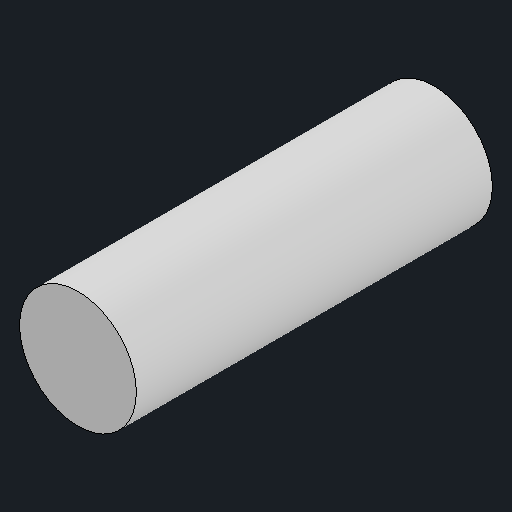
# Autodesk Inventor part: ASH125-bellows-grip-envelope
Saved by Autodesk Inventor 2027.1 (Build 311270010, 270A)
## iProperties
Created: 2026-11-14
Part Number: ASH125-bellows-grip-envelope
Material: Generic
Description: ASH125 SFR deployed grip layout envelope
Document SubType Name: Modeling
Designer: queezz
Density: 1 g/cm^3
Appearance: Default
Author: queezz
Autodesk Inventor part; units mm, degrees
ref_plane "YZ Plane" through (0, 0, 0) normal (1, 0, 0) x (0, 1, 0)
ref_plane "XZ Plane" through (0, 0, 0) normal (0, 1, 0) x (-1, 0, 0)
ref_plane "Grip section plane" through (0, 0, 0) normal (0, 0, 1) x (1, 0, 0)
sketch "Grip section" plane through (0, 0, 0) normal (0, 0, 1) x (1, 0, 0)
  circle A0 centre (0, 0) radius 10
  dimension "d0" = 61
  constraints: 1 centre point
extrude "Grip envelope" add sketch "Grip section" along normal blind 61
body "Solid1"
